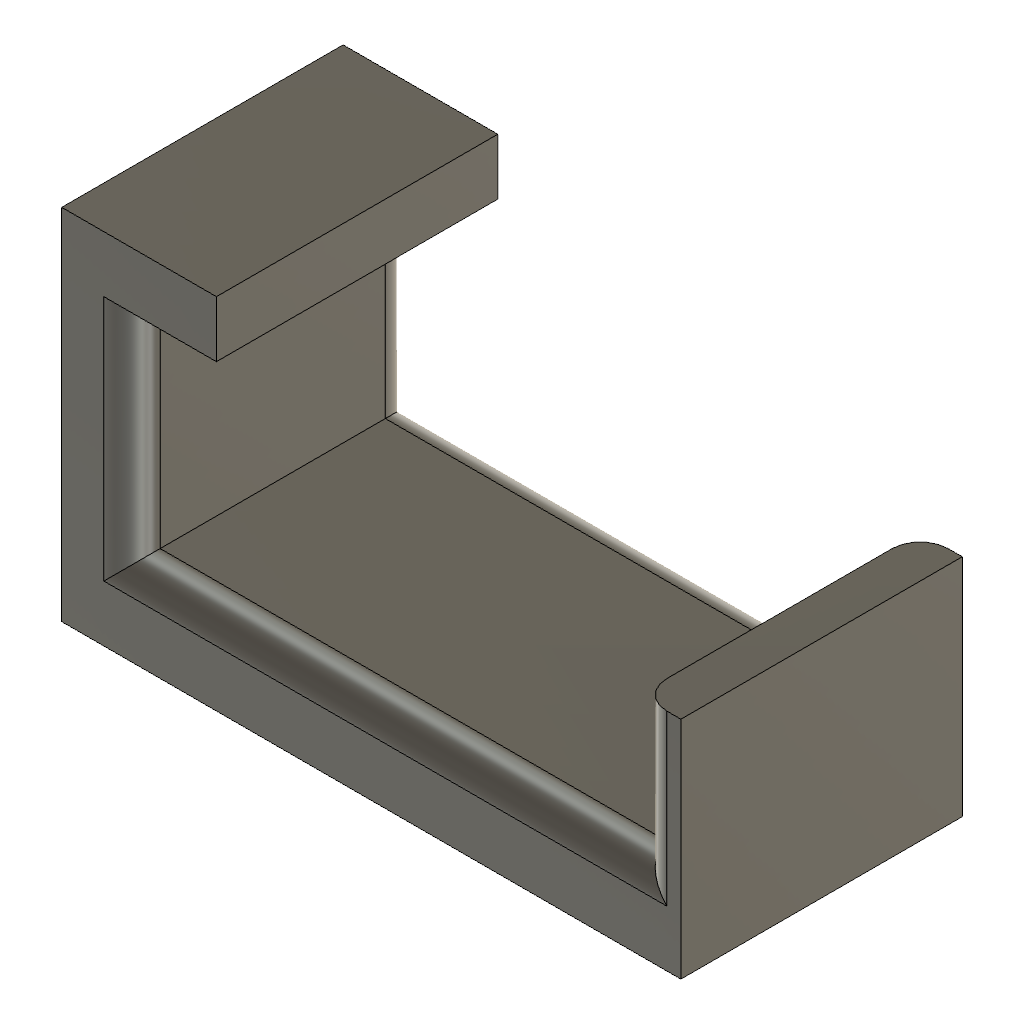
Driver Holder CLAMP (Autodesk Fusion 360 design; units mm, degrees)
Autodesk Fusion 360 part; units mm, degrees
sketch "Sketch1" plane through (0, 0, 0) normal (1, 0, 0) x (0, 1, 0)
  line L0 (0, 0) -> (20, 0)
  line L1 (20, 0) -> (20, 15.5)
  line L2 (20, 15.5) -> (0, 15.5)
  line L3 (0, 15.5) -> (0, 0)
  line L4 (0, 15.5) -> (20, 15.5)
  line L5 (20, 15.5) -> (20, 19.5)
  line L6 (20, 19.5) -> (0, 19.5)
  line L7 (0, 19.5) -> (0, 15.5)
  line L8 (0, 0) -> (20, 0)
  line L9 (20, 0) -> (20, -6)
  line L10 (20, -6) -> (0, -6)
  line L11 (0, -6) -> (0, 0)
  dimension "d1" = 20
  dimension "d2" = 15.5
  dimension "d5" = 4
  dimension "d6" = 20
  dimension "d7" = 6
  constraint horizontal L0
  constraint vertical L1
  constraint horizontal L2
  constraint vertical L3
  constraint coincident L0.start L3.end
  constraint horizontal L4
  constraint vertical L5
  constraint horizontal L6
  constraint vertical L7
  constraint horizontal L8
  constraint vertical L9
  constraint horizontal L10
  constraint vertical L11
  measures "d1" distance of L0.start L0.end
  measures "d2" distance of L0.start L2.end
  measures "d5" distance of L2.end L6.end
  measures "d6" distance of L0.start L0.end
  measures "d7" distance of L0.start L10.end
extrude "Extrude1" add sketch "Sketch1" against normal blind 5
extrude "Extrude2" add sketch "Sketch1" along normal blind 6 contours L2 L4 L5 L6 L7
extrude "Extrude3" add sketch "Sketch1" along normal blind 39 contours L0 L8 L9 L10 L11
sketch "Sketch2" plane through (0, 0, 0) normal (0, 0, 1) x (-1, 0, 0)
  line L0 (0, -20) -> (0, 0)
  line L1 (0, 0) -> (-39, 0)
  line L2 (-39, 0) -> (-39, -20)
  line L3 (-39, -20) -> (0, -20)
  line L4 (-39, -20) -> (-36, -20)
  line L5 (-36, -20) -> (-36, 0)
  line L6 (-36, 0) -> (-39, 0)
  line L7 (-39, 0) -> (-39, -20)
  dimension "d12" = 3
  constraint horizontal L4
  constraint vertical L5
  constraint horizontal L6
  constraint vertical L7
  constraint coincident L2.end L3.start
  measures "d12" distance of L2.end L4.end
extrude "Extrude4" add sketch "Sketch2" along normal blind 10 contours L1 L2 L3 L4 L5 L6 L7
fillet "Fillet1" radius 2 6 edges at (0, 0, 7.75) (18, 0, 0) (36, 0, 5) (0, 20, 7.75) (18, 20, 0) (36, 20, 5)
